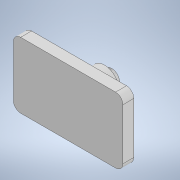
# Autodesk Inventor part: CAP_ARC_AX_4.2_fara_ax.stl
Saved by Autodesk Inventor 2020 (Build 240168000, 168)
## iProperties
Created: 2023-04-30
Part Number: CAP_ARC_AX_4.2_fara_ax.stl
Material: Generic
Document SubType Name: Modeling
Designer: user
Density: 1 g/cm^3
Appearance: Default
Author: user
Autodesk Inventor part; units mm, degrees
ref_plane "YZ Plane" through (0, 0, 0) normal (1, 0, 0) x (0, 1, 0)
ref_plane "XZ Plane" through (0, 0, 0) normal (0, 1, 0) x (-1, 0, 0)
ref_plane "XY Plane" through (0, 0, 0) normal (0, 0, 1) x (1, 0, 0)
sketch "Sketch1" plane through (0, 0, 0) normal (0, 0, 1) x (1, 0, 0)
  circle A0 centre (0, 0) radius 2.1
  dimension "d0" = 4.2
  constraints: 1 centre point, 1 coincident
  measures "d0" diameter of A0
extrude "Extrusion1" add sketch "Sketch1" along normal blind 20 and the other way blind 18
sketch "Sketch2" plane through (0, 0, 20) normal (0, 0, 1) x (1, 0, 0)
  circle A0 centre (0, 0) radius 3.9
  dimension "d3" = 7.8
  constraints: 1 centre point, 1 coincident
  measures "d3" diameter of A0
extrude "Extrusion2" add sketch "Sketch2" against normal blind 7
sketch "Sketch3" plane through (0, 0, 20) normal (0, 0, 1) x (1, 0, 0)
  line L0 (-15, -9) -> (15, -9)
  line L1 (15, -9) -> (15, 9)
  line L2 (15, 9) -> (-15, 9)
  line L3 (-15, 9) -> (-15, -9)
  line L4 (-15, -9) -> (15, 9) construction
  line L5 (15, -9) -> (-15, 9) construction
  point P0 (0, 0)
  point P1 (0, 0)
  dimension "d15" = 18
  dimension "d16" = 30
  constraints: 12 end point, 2 parallel, 1 coincident, 1 horizontal, 1 midpoint, 1 perpendicular
  measures "d15" distance of L0.end L1.end
  measures "d16" distance of L1.end L2.end
extrude "Extrusion3" add sketch "Sketch3" along normal blind 3
fillet "Fillet1" radius 4 1 edges at (-3.9, 0, 20)
fillet "Fillet2" radius 2 1 edges at (-2.1, 0, 13)
fillet "Fillet5" radius 2 4 edges at (-15, -9, 21.5) (-15, 9, 21.5) (15, 9, 21.5) (15, -9, 21.5)
sketch "Sketch4" plane through (0, 0, -18) normal (0, 0, -1) x (-1, 0, 0)
  circle A0 centre (0, 0) radius 2.1
  constraints: 1 centre point, 1 coincident
extrude "Extrusion4" cut sketch "Sketch4" against normal up to surface (38 mm away)
body "Solid1"
